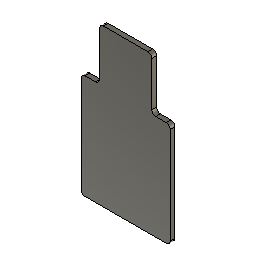
RESPALDAR (Autodesk Fusion 360 design; units mm, degrees)
part number: 2026-06-03-16-50-07-310
Autodesk Fusion 360 part; units mm, degrees
sketch "Sketch1" plane through (0, 0, 0) normal (0, 1, 0) x (1, 0, 0)
  line L0 (0, 0) -> (341, 0)
  line L1 (341, 0) -> (341, -400)
  line L2 (0, -400) -> (0, 0)
  line L3 (70.5, -400) -> (270.5, -400)
  line L4 (270.5, -400) -> (270.5, -600)
  line L5 (270.5, -600) -> (70.5, -600)
  line L6 (70.5, -600) -> (70.5, -400)
  line L7 (341, -400) -> (270.5, -400)
  line L8 (70.5, -400) -> (0, -400)
  dimension "d1" = 341
  dimension "d2" = 400
  dimension "d3" = 200
  dimension "d4" = 200
  dimension "d9" = 70.5
  constraint horizontal L0
  constraint vertical L1
  constraint horizontal L7
  constraint vertical L2
  constraint coincident L0.start L2.end
  constraint horizontal L3
  constraint vertical L4
  constraint horizontal L5
  constraint vertical L6
  constraint collinear L7 L8
  measures "d1" distance of L0.start L0.end
  measures "d2" distance of L0.end L1.end
  measures "d3" distance of L3.end L4.end
  measures "d4" distance of L4.end L5.end
  measures "d9" distance of L1.end L3.end
extrude "Extrude1" add sketch "Sketch1" along normal blind 18
fillet "Fillet1" radius 15 8 edges at (270.5, 9, 600) (70.5, 9, 600) (341, 9, 400) (0, 9, 400) (341, 9, 0) (0, 9, 0) (270.5, 9, 400) (70.5, 9, 400)
